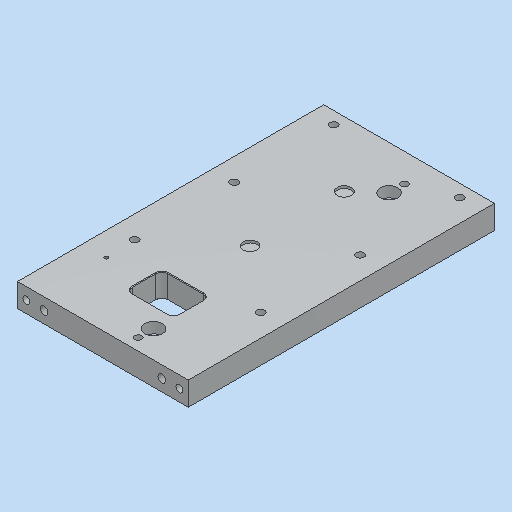
# Autodesk Inventor part: MM0948AN180_G01_103
Saved by Autodesk Inventor 2023.3 (Build 273359000, 359)
## iProperties
Part Number: MM0948AN180_G01_103
Material: 3.3547 AlMg4,5Mn0,7 - AW 5083
Description: =<RBPARTNOTITLE2>
Document SubType Name: Modeling
Designer: ric7an
Mass: 1929.37 g
Surface Area: 984.238 cm^2
Volume: 714.581 cm^3
Density: 2.7 g/cm^3
Appearance: Aluminium AnP
Created: 2023-03-23
RBDOCUMENTTYPE: DRF
RBDOCUMENTVERSION: 00
RBDRAWINGMAINSCALE: 1:1
RBDRAWINGMISSINGSPEC: --
RBDRAWINGVOLUME: --
RBGBEDGESIN1: +0,5
RBGBEDGESIN2: +0,2
RBGBEDGESOUT1: -0,3
RBGBEDGESOUT2: -0,1
RBMATERIAL: =<Material>
RBMATMEETS: --
RBMATNO: =<Part Number>
RBPARTMADEOF: 20 x 260 x 145 (FM)
RBPARTNO: SIEHE MNR
RBPARTNOTITLE1: manufactured part
RBPARTNOTITLE2: Anfertigungsteil
RBPARTSAFETYINDICATOR: --
RBSURFACE: anodised colourless
RBSURFACE2: eloxiert farblos
RBZEDGESNORM: ISO13715:2002-06
RBZGENDIMCLASS: m
RBZGENDIMNORM: ISO 2768-1:1989-11
RBZGENGEOCLASS: H
RBZGENGEONORM: ISO 2768-2:1989-11
RBZSURFACENORM: ISO13D2:2002-02
RBZTOLERANCENORM: ISO 14405-1:2010-12
AnP_Material: =<Material>
AnP_TemplVers: 20190222
AnP_Kategorie: 1
MaxAbmaße: 20 x 260 x 145 (FM)
AnP_Kommentar_aktuell: =<Comments>
AnP_Material_aktuell: =<Material>
Author: FH/Wi
Keywords: =<RBPARTMADEOF>
Comments: =<RBSURFACE2>
Revision Number: 01
Autodesk Inventor part; units mm, degrees
ref_plane "YZ Plane" through (0, 0, 0) normal (1, 0, 0) x (0, 1, 0)
ref_plane "XZ Plane" through (0, 0, 0) normal (0, 1, 0) x (-1, 0, 0)
ref_plane "XY Plane" through (0, 0, 0) normal (0, 0, 1) x (1, 0, 0)
sketch "Skizze1" plane through (0, 0, 0) normal (0, 0, 1) x (1, 0, 0)
  line L0 (-72.5, 260) -> (72.5, 260)
  line L1 (72.5, 260) -> (72.5, 0)
  line L2 (72.5, 0) -> (-72.5, 0)
  line L3 (-72.5, 0) -> (-72.5, 260)
  line L4 (0, 312) -> (0, -52) projected
  line L5 (-101.5, 0) -> (101.5, 0) projected
  point P0 (0, 0)
  dimension "d0" = 260
  dimension "d1" = 145
  constraints: 8 end point, 2 parallel, 1 collinear, 1 horizontal, 1 perpendicular, 1 other
  measures "d0" distance of L0.end L1.end
  measures "d1" distance of L0.start L0.end
extrude "Extrusion1" add sketch "Skizze1" along normal mid plane 20
sketch "Skizze2" plane through (0, 0, -10) normal (0, 0, -1) x (1, 0, 0)
  line L0 (0, 69.7) -> (0, -418.2) projected
  line L1 (101.5, 0) -> (-101.5, 0) projected
  line L2 (-72.5, -260) -> (72.5, -260) projected
  line L3 (-72.5, 0) -> (-72.5, -260) projected
  line L4 (72.5, -260) -> (72.5, 0) projected
  point P0 (0, 0)
  point P1 (-53.5, -80.5)
  point P2 (-53.5, -165)
  point P3 (-53.5, -249.5)
  point P4 (53.5, -249.5)
  point P5 (53.5, -165)
  point P6 (53.5, -80.5)
  dimension "d5" = 84.5
  dimension "d47" = 10.5
  dimension "d69" = 19
  dimension "d71" = 19
  dimension "d73" = 169
  constraints: 4 vertical alignment, 3 horizontal alignment
  measures "d5" distance of point (53.5, -249.5) point (53.5, -165)
  measures "d47" distance from line of L2 point (53.5, -249.5)
  measures "d69" distance from line of point (-53.5, -80.5) L3
  measures "d71" distance from line of L4 point (53.5, -80.5)
  measures "d73" distance of point (53.5, -249.5) point (53.5, -80.5)
hole "Bohrung1" at (-53.5, 80.5, -10) at (-53.5, 165, -10) at (-53.5, 249.5, -10) at (53.5, 249.5, -10) at (53.5, 165, -10) at (53.5, 80.5, -10) direction (0, 0, 1) diameter 6.6 end through all counterbore diameter 11 counterbore depth 6.8 clearance for "Inbusschraube ISO 4762  versenkt" size "M6" standard "ISO"
sketch "Skizze3" plane through (0, 0, 10) normal (0, 0, 1) x (-1, 0, 0)
  line L0 (72.5, 0) -> (-72.5, 0) projected
  line L1 (0, -397.2) -> (0, 66.2) projected
  line L2 (-72.5, -260) -> (72.5, -260) projected
  line L3 (72.5, -260) -> (72.5, 0) projected
  point P0 (0, 0)
  point P1 (0, -125)
  point P2 (0, -205)
  dimension "d25" = 80
  dimension "d68" = 55
  dimension "d70" = 72.5
  constraints: 1 vertical alignment
  measures "d25" distance of point (0, -125) point (0, -205)
  measures "d68" distance from line of L2 point (0, -205)
  measures "d70" distance from line of L3 point (0, -125)
hole "Bohrung2" at (0, 125, 10) at (0, 205, 10) direction (0, 0, -1) diameter 12 depth 2.1
sketch "Skizze4" plane through (0, 0, 10) normal (0, 0, 1) x (-1, 0, 0)
  line L0 (0, -343.2) -> (0, 57.2) projected
  line L1 (-72.5, -260) -> (72.5, -260) projected
  line L2 (72.5, 0) -> (-72.5, 0) projected
  point P0 (0, 0)
  point P1 (-20, -10)
  point P2 (-20, -23)
  point P3 (-20, -223)
  point P4 (-20, -236)
  dimension "d29" = 13
  dimension "d49" = 10
  dimension "d74" = 200
  dimension "d75" = 20
  dimension "d81" = 13
  constraints: 3 vertical alignment
  measures "d29" distance of point (-20, -23) point (-20, -10)
  measures "d49" distance from line of L2 point (-20, -10)
  measures "d74" distance of point (-20, -23) point (-20, -223)
  measures "d75" distance from line of point (-20, -23) L0
  measures "d81" distance of point (-20, -236) point (-20, -223)
hole "Bohrung3" at (20, 23, 10) at (20, 223, 10) direction (0, 0, -1) diameter 9 end through all counterbore diameter 15 counterbore depth 9 clearance for "Inbusschraube ISO 4762  versenkt" size "M8" standard "ISO"
hole "Bohrung4" at (20, 10, 10) at (20, 236, 10) direction (0, 0, -1) diameter 6 end through all
sketch "Skizze5" plane through (-72.5, 0, -10) normal (0, 1, 0) x (-1, 0, 0)
  line L0 (-198.5, 10) -> (53.5, 10) projected
  line L1 (-72.5, -4) -> (-72.5, 24) projected
  point P0 (-72.5, 10)
  point P1 (-137.5, 10)
  point P2 (-122.5, 10)
  point P3 (-22.5, 10)
  point P4 (-7.5, 10)
  dimension "d45" = 130
  dimension "d46" = 100
  dimension "d50" = 15
  constraints: 4 point on line, 1 symmetric about line
  measures "d45" distance of point (-7.5, 10) point (-137.5, 10)
  measures "d46" distance of point (-22.5, 10) point (-122.5, 10)
  measures "d50" distance of point (-122.5, 10) point (-137.5, 10)
hole "Bohrung5" at (50, 0, 0) at (-50, 0, 0) direction (0, 1, 0) diameter 6.647 depth 22.2 tip angle 118 thread size "M8x1.25" designation "M8" class "6H" standard "ISO Metric profile"
hole "Bohrung6" at (65, 0, 0) at (-65, 0, 0) direction (0, 1, 0) diameter 6 depth 22.2 tip angle 118
sketch "Skizze6" plane through (0, 0, 10) normal (0, 0, 1) x (1, 0, 0)
  line L0 (-20, 70) -> (20, 70)
  line L1 (20, 70) -> (20, 40)
  line L2 (20, 40) -> (-20, 40)
  line L3 (-20, 40) -> (-20, 70)
  line L4 (0, 312) -> (0, -52) projected
  line L5 (-101.5, 0) -> (101.5, 0) projected
  point P0 (0, 0)
  dimension "d77" = 30
  dimension "d78" = 40
  dimension "d83" = 70
  constraints: 8 end point, 2 parallel, 1 horizontal, 1 perpendicular, 1 other
  measures "d77" distance of L0.end L1.end
  measures "d78" distance of L0.start L0.end
  measures "d83" distance between parallel lines of L0 L5
extrude "Extrusion2" cut sketch "Skizze6" against normal through all
sketch "Skizze7" plane through (0, 0, 10) normal (0, 0, 1) x (1, 0, 0)
  line L0 (72.5, 0) -> (72.5, 260) projected
  line L1 (-72.5, 0) -> (72.5, 0) projected
  line L2 (-72.5, 260) -> (-72.5, 0) projected
  point P0 (0, 0)
  point P1 (-52.5, 55.2)
  dimension "d85" = 55.2
  dimension "d93" = 20
  measures "d85" distance from line of L1 point (-52.5, 55.2)
  measures "d93" distance from line of point (-52.5, 55.2) L2
hole "Bohrung7" at (-52.5, 55.2, 10) direction (0, 0, -1) diameter 3.242 end through all thread size "M4x0.7" designation "M4" class "6H" standard "ISO Metric profile"
fillet "Rundung1" radius 5 4 edges at (-20, 40, 0) (-20, 70, 0) (20, 70, 0) (20, 40, 0)
chamfer "Fase1" distance 0.5 angle 45 16 edges at (0, 40, 10) (-18.5355, 41.4645, 10) (-20, 55, 10) (-18.5355, 68.5355, 10) (0, 70, 10) (18.5355, 68.5355, 10) (20, 55, 10) (18.5355, 41.4645, 10) (0, 40, -10) (18.5355, 41.4645, -10) (20, 55, -10) (18.5355, 68.5355, -10) (0, 70, -10) (-18.5355, 68.5355, -10) (-20, 55, -10) (-18.5355, 41.4645, -10)
equation "\"d81\" = d29"
equation "\"d50\" = -0.5 * d46 + 0.5 * d45"
